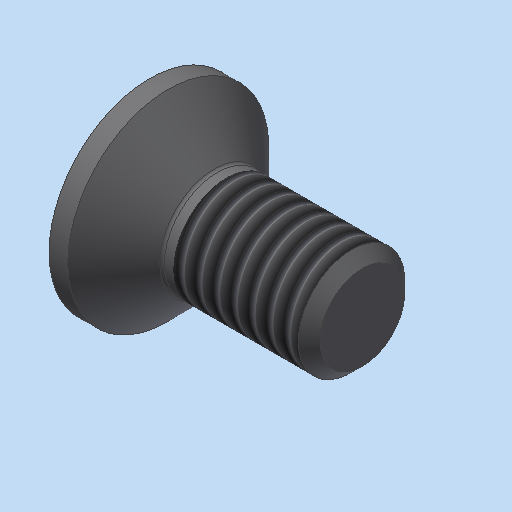
# Autodesk Inventor part: Senkschraube_ISO_10642___M6x12
Saved by Autodesk Inventor 2023.3 (Build 273359000, 359)
## iProperties
Shininess: 64.0
Length Units: 11269
Angle Units: 11279
Time Units: 11290
Mass Units: 11283
Length Display Precision: 3
Angle Display Precision: 2
Compacted: True
Part Number: Senkschraube_ISO_10642___M6x12
Document SubType Name: Modeling
Created: 2004-03-30
Material: xStahl_AnP_Dummymaterial
Description: =<RBPARTNOTITLE2>
Vendor: NORM8
Designer: S.Riedelsheimer
Manufacturer: Standard
Standards Organization: Custom
Density: 7.85 g/cm^3
Mass: 3.68098 g
Surface Area: 4.47974 cm^2
Volume: 0.468915 cm^3
Appearance: Stahl - normal AnP
DOC_ID: 5 F45 Senkschraube_ISO_10642___M6x12
GAIN_REFID: 20__Senkschraube_ISO_10642___M6x12:81C07
Control State: 0
Master: False
Checked Out: False
CNS_NB: Senkschraube ISO 10642 - M6x12
CNS_NN: ISO 10642
CNS_NT: Senkschrauben mit Innensechskant
CNS_NBSYN: Senkschraube $NENN.
CNS_LINA: Senkschraube ISO 10642 - M6x12
CNS_D: 6.000
CNS_D3: 4.773
CNS_P: 1.000
CNS_L: 12.000
CNS_S: 4.000
CNS_DK: 11.340
CNS_K: 3.720
CNS_T: 2.200
CNS_R: 0.250
CNS_LS: 0.000
CNS_LG: 0.000
CNS_NENN: ISO 10642 - M6x12
CNS_YW: 1.571
CNS_YC: 1.050
CNS_KT: DUMMY
PSOL_IDENT_0: {C:\partsolutions8\data\23d-libs\bosch_bamberg\schrauben\senkschrauben\iso_10642.prj},168 {M=Nenngew
PSOL_IDENT_1: inde},{VTYP=3D},{NB=Senkschraube ISO 10642 - M6x12},{NN=ISO 10642},{DATE=26.11.2003},{GEOMDATE=26.11
PSOL_IDENT_2: .2003},{VERSION=v1},{LINEID=300},{LINESUBID=-1},{WBVAR=}  {NB=Senkschraube ISO 10642 - M6x12},{LINA=
PSOL_IDENT_3: Senkschraube ISO 10642 - M6x12},{KT=DUMMY},{IDNR=},{D=6.000},{D3=4.773},{P=1.000},{L=12.000},{S=4.00
PSOL_IDENT_4: 0},{DK=11.340},{K=3.720},{T=2.200},{R=0.250},{LS=0.000},{LG=0.000},{NENN=ISO 10642 - M6x12},{YW=1.57
PSOL_IDENT_5: 079},{YC=1.049984}
DEF_STKID: T21133
Bezeichnung1: Senkschraube ISO 10642 - M6x12
Bezeichnung2: Senkschrauben mit Innensechskant
RBPARTNOTITLE2: Senkschrauben mit Innensechskant
RBPARTMADEOF: ISO 10642 - M6x12
RBPARTNOTITLE1: Hexagon socket countersunk head screws
RBDRAWINGMISSINGSPEC: --
AnP_Kategorie: 4
Density: 0.0
Volumn: 0.0
Area: 0.0
PropertySet Name: Model Information
Title: Senkschraube ISO 10642 - M6x12
Author: S.Riedelsheimer
Keywords: =<RBPARTMADEOF>
Comments: =<RBSURFACE2>
Revision Number: 01
Autodesk Inventor part; units mm, degrees
sketch "Sketch_1" plane through (0, 0, 0) normal (0, 0, 1) x (1, 0, 0)
  line L0 (0.6188, 0) -> (12, 0)
  line L1 (12, 0) -> (12, -2.3865)
  line L2 (12, -2.3865) -> (11.3865, -3)
  line L3 (11.3865, -3) -> (3.8236, -3)
  arc A0 (3.8236, -3) -> (3.6468, -3.0732) centre (3.8236, -3.25) ccw
  line L4 (3.6468, -3.0732) -> (1.05, -5.67)
  line L5 (1.05, -5.67) -> (0, -5.67)
  line L6 (0, -5.67) -> (0, -2.3094)
  line L7 (0, -2.3094) -> (0.6188, 0)
  line L8 (0.6188, 0) -> (12, 0)
  constraints: 18 end point, 2 point on circle, 1 centre point
revolve "Drehung1" add sketch "Sketch_1" angle 360 about axis through (0.6188, 0, 0) along (1, 0, 0)
thread "Gewinde1" size "M6x1" class "6g" standard "ANSI Metric M Profile" length 7.053
sketch "Sketch_3" plane through (0, 0, 0) normal (1, 0, 0) x (0, 1, 0)
  line L0 (0, 2.3094) -> (-2, 1.1547)
  line L1 (-2, 1.1547) -> (-2, -1.1547)
  line L2 (-2, -1.1547) -> (0, -2.3094)
  line L3 (0, -2.3094) -> (2, -1.1547)
  line L4 (2, -1.1547) -> (2, 1.1547)
  line L5 (2, 1.1547) -> (0, 2.3094)
  constraints: 12 end point
extrude "Extrusion1" cut sketch "Sketch_3" along normal blind 2.2
ref_plane "IP1_XY" through (0, 0, 0) normal (1, 0, 0) x (0, 0, -1)
ref_plane "IP1_YZ" through (0, 0, 0) normal (0, 0, -1) x (0, 1, 0)
ref_plane "IP2_XY" through (12, 0, 0) normal (1, 0, 0) x (0, 0, -1)
ref_plane "IP2_YZ" through (12, 0, 0) normal (0, 0, -1) x (0, 1, 0)
